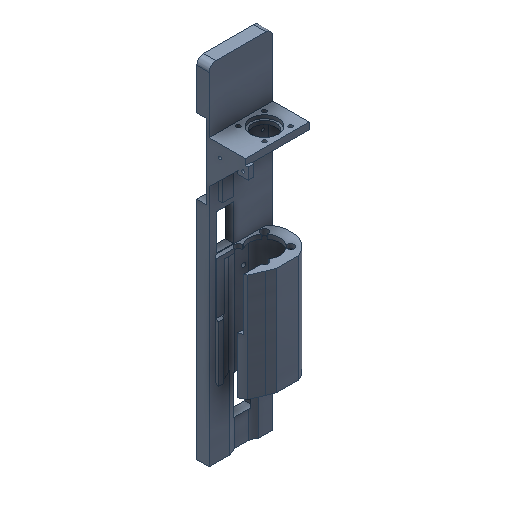
# Autodesk Inventor part: OT2-Pipette V0.5 - frame
Saved by Autodesk Inventor 2025.5 (Build 295498000, 498)
## iProperties
Created: 2026-11-20
Part Number: OT2-Pipette V0.5 - frame
Material: Generisch
Description: printed frame: mount wall with 3 M3 inserts, sleeve + ledge, header window, motor shelf (PETG/ASA)
Document SubType Name: Modeling
Designer: benir
Density: 1 g/cm^3
Appearance: Light Steel Blue
Author: benir
Autodesk Inventor part; units mm, degrees
ref_plane "WP mount face" through (-9.5, 0, 0) normal (1, 0, 0) x (0, 1, 0)
ref_plane "WP pipette x" through (8.2, 0, 0) normal (1, 0, 0) x (0, 1, 0)
ref_plane "WP pipette z" through (0, 0, -3.46) normal (0, 0, 1) x (1, 0, 0)
ref_plane "WP motor seat" through (0, 119, 0) normal (0, 1, 0) x (-1, 0, 0)
ref_plane "y=ins_top_y" through (0, 46, 0) normal (0, 1, 0) x (-1, 0, 0)
ref_plane "z=ins_z" through (0, 0, 13.25) normal (0, 0, 1) x (1, 0, 0)
ref_plane "z=-ins_z" through (0, 0, -13.25) normal (0, 0, 1) x (1, 0, 0)
ref_plane "y=ins_bot_y" through (0, -43, 0) normal (0, 1, 0) x (-1, 0, 0)
sketch "mount wall" plane through (-9.5, 0, 0) normal (1, 0, 0) x (0, 1, 0)
  line L0 (-49, -18.75) -> (156.35, -18.75)
  line L1 (156.35, -18.75) -> (156.35, 18.75)
  line L2 (156.35, 18.75) -> (-49, 18.75)
  line L3 (-49, 18.75) -> (-49, -18.75)
  line L4 (0, -26.25) -> (0, 26.25) projected
  line L5 (-90.07, 0) -> (197.42, 0) projected
  point P0 (0, 0)
  dimension "d10" = 205.35
  dimension "d11" = 37.5
  dimension "d12" = 49
  dimension "d13" = 18.75
  constraints: 8 end point, 2 parallel, 1 horizontal, 1 perpendicular
  measures "d10" distance of L0.start L0.end
  measures "d11" distance of L2.end L0.start
  measures "d12" horizontal distance of point (0, 0) L2.end
  measures "d13" vertical distance of point (0, 0) L0.start
extrude "Extrusion2" add sketch "mount wall" along normal blind 7.3
fillet "wall top edges" radius 4 2 edges at (-5.85, 156.35, 18.75) (-5.85, 156.35, -18.75)
ref_plane "y=sleeve_y0" through (0, -6, 0) normal (0, 1, 0) x (-1, 0, 0)
sketch "sleeve outline" plane through (0, -6, 0) normal (0, 1, 0) x (-1, 0, 0)
  arc A0 (-20.2, -6.2935) -> (3.8, -6.2935) centre (-8.2, -3.46) ccw construction
  arc A1 (-1.2, 13.79) -> (-15.2, 13.79) centre (-8.2, 2.54) ccw construction
  line L0 (3.8, -6.2935) -> (3.8, 1.71) construction
  line L1 (3.8, 1.71) -> (1.58, 7.29) construction
  line L2 (1.58, 7.29) -> (-1.2, 13.79) construction
  line L3 (-15.2, 13.79) -> (-17.98, 7.29) construction
  line L4 (-17.98, 7.29) -> (-20.2, 1.71) construction
  line L5 (-20.2, 1.71) -> (-20.2, -6.2935) construction
  arc A2 (-23.5, -6.6548) -> (7.1, -6.6548) centre (-8.2, -3.46) ccw
  line L6 (7.1, -6.6548) -> (7.1, 2.3423)
  line L7 (7.1, 2.3423) -> (4.6307, 8.549)
  line L8 (4.6307, 8.549) -> (1.4503, 15.9853)
  arc A3 (1.4503, 15.9853) -> (-17.8503, 15.9853) centre (-8.2, 2.54) ccw
  line L9 (-17.8503, 15.9853) -> (-21.0307, 8.549)
  line L10 (-21.0307, 8.549) -> (-23.5, 2.3423)
  line L11 (-23.5, 2.3423) -> (-23.5, -6.6548)
  point P0 (0, 0)
  dimension "sw_l" = 12.8
  dimension "d18" = 3.46
  dimension "d19" = 8.2
  dimension "d20" = 2.54
  dimension "d21" = 8.2
  dimension "d22" = 6.2935
  dimension "d23" = 20.2
  dimension "d24" = 3.8
  dimension "d25" = 13.79
  dimension "d26" = 15.2
  dimension "d27" = 1.2
  dimension "d28" = 1.71
  dimension "d29" = 3.8
  dimension "d30" = 7.29
  dimension "d31" = 1.58
  dimension "d32" = 7.29
  dimension "d33" = 17.98
  dimension "d34" = 1.71
  dimension "d35" = 20.2
  dimension "d36" = 3.3
  constraints: 24 end point, 8 point on circle, 4 centre point, 7 other
  measures "d18" vertical distance of point (0, 0) A0.centre
  measures "d19" horizontal distance of point (0, 0) A0.centre
  measures "d20" vertical distance of point (0, 0) A1.centre
  measures "d21" horizontal distance of point (0, 0) A1.centre
  measures "d22" vertical distance of point (0, 0) L5.end
  measures "d23" horizontal distance of point (0, 0) L5.end
  measures "d24" horizontal distance of point (0, 0) L0.start
  measures "d25" vertical distance of point (0, 0) L3.start
  measures "d26" horizontal distance of point (0, 0) L3.start
  measures "d27" horizontal distance of point (0, 0) L2.end
  measures "d28" vertical distance of point (0, 0) L0.end
  measures "d29" horizontal distance of point (0, 0) L0.end
  measures "d30" vertical distance of point (0, 0) L1.end
  measures "d31" horizontal distance of point (0, 0) L1.end
  measures "d32" vertical distance of point (0, 0) L3.end
  measures "d33" horizontal distance of point (0, 0) L3.end
  measures "d34" vertical distance of point (0, 0) L4.end
  measures "d35" horizontal distance of point (0, 0) L4.end
  measures "d36" distance between parallel lines of L6 L0
extrude "sleeve and ledge" add sketch "sleeve outline" along normal blind 63.5
ref_plane "y=mot_front - shelf_t" through (0, 115, 0) normal (0, 1, 0) x (-1, 0, 0)
sketch "motor shelf" plane through (0, 115, 0) normal (0, 1, 0) x (-1, 0, 0)
  line L0 (2.7, -18.75) -> (-19.2, -18.75)
  line L1 (-19.2, -18.75) -> (-19.2, 18.75)
  line L2 (-19.2, 18.75) -> (2.7, 18.75)
  line L3 (2.7, 18.75) -> (2.7, -18.75)
  line L4 (0, -26.726) -> (0, 26.726) projected
  line L5 (16.1, 0) -> (-30.1, 0) projected
  point P0 (0, 0)
  dimension "d40" = 21.9
  dimension "d41" = 37.5
  dimension "d42" = 2.7
  dimension "d43" = 18.75
  constraints: 8 end point, 2 parallel, 1 horizontal, 1 perpendicular
  measures "d40" distance of L0.start L0.end
  measures "d41" distance of L2.end L0.start
  measures "d42" horizontal distance of point (0, 0) L2.end
  measures "d43" vertical distance of point (0, 0) L0.start
extrude "Extrusion4" add sketch "motor shelf" along normal blind 4
ref_plane "z=-env_z" through (0, 0, -18.75) normal (0, 0, 1) x (1, 0, 0)
sketch "gusset -z" plane through (0, 0, -18.75) normal (0, 0, 1) x (1, 0, 0)
  line L0 (-2.7, 115) -> (19.2, 115)
  line L1 (19.2, 115) -> (-2.7, 93.6)
  line L2 (-2.7, 93.6) -> (-2.7, 115)
  point P0 (0, 0)
  dimension "d47" = 115
  dimension "d48" = 2.7
  dimension "d49" = 115
  dimension "d50" = 19.2
  dimension "d51" = 93.6
  dimension "d52" = 2.7
  constraints: 6 end point
  measures "d47" vertical distance of point (0, 0) L0.start
  measures "d48" horizontal distance of point (0, 0) L0.start
  measures "d49" vertical distance of point (0, 0) L0.end
  measures "d50" horizontal distance of point (0, 0) L0.end
  measures "d51" vertical distance of point (0, 0) L1.end
  measures "d52" horizontal distance of point (0, 0) L1.end
extrude "Extrusion5" add sketch "gusset -z" along normal blind 2.5
ref_plane "z=env_z - gusset_t" through (0, 0, 16.25) normal (0, 0, 1) x (1, 0, 0)
sketch "gusset +z" plane through (0, 0, 16.25) normal (0, 0, 1) x (1, 0, 0)
  line L0 (-2.7, 115) -> (19.2, 115)
  line L1 (19.2, 115) -> (-2.7, 93.6)
  line L2 (-2.7, 93.6) -> (-2.7, 115)
  point P0 (0, 0)
  dimension "d56" = 115
  dimension "d57" = 2.7
  dimension "d58" = 115
  dimension "d59" = 19.2
  dimension "d60" = 93.6
  dimension "d61" = 2.7
  constraints: 6 end point
  measures "d56" vertical distance of point (0, 0) L0.start
  measures "d57" horizontal distance of point (0, 0) L0.start
  measures "d58" vertical distance of point (0, 0) L0.end
  measures "d59" horizontal distance of point (0, 0) L0.end
  measures "d60" vertical distance of point (0, 0) L1.end
  measures "d61" horizontal distance of point (0, 0) L1.end
extrude "Extrusion6" add sketch "gusset +z" along normal blind 2.5
ref_plane "x=wall_x1 - cut_over" through (-3.2, 0, 0) normal (1, 0, 0) x (0, 1, 0)
sketch "rib" plane through (-3.2, 0, 0) normal (1, 0, 0) x (0, 1, 0)
  line L0 (84, 6.3) -> (115, 6.3)
  line L1 (115, 6.3) -> (115, 13.2)
  line L2 (115, 13.2) -> (84, 13.2)
  line L3 (84, 13.2) -> (84, 6.3)
  line L4 (0, -26.726) -> (0, 26.726) projected
  line L5 (-90.07, 0) -> (197.42, 0) projected
  point P0 (0, 0)
  dimension "d65" = 31
  dimension "d66" = 6.9
  dimension "d67" = 84
  dimension "d68" = 6.3
  constraints: 8 end point, 2 parallel, 1 horizontal, 1 perpendicular
  measures "d65" distance of L0.start L0.end
  measures "d66" distance of L2.end L0.start
  measures "d67" horizontal distance of point (0, 0) L2.end
  measures "d68" vertical distance of point (0, 0) L0.start
extrude "rib behind the top-block relief" add sketch "rib" along normal blind 3.2
ref_plane "y=body_bottom - body_cut_below" through (0, -96, 0) normal (0, 1, 0) x (-1, 0, 0)
sketch "body clearance outline" plane through (0, -96, 0) normal (0, 1, 0) x (-1, 0, 0)
  arc A0 (-20.2, -6.2935) -> (3.8, -6.2935) centre (-8.2, -3.46) ccw construction
  arc A1 (-1.2, 13.79) -> (-15.2, 13.79) centre (-8.2, 2.54) ccw construction
  line L0 (3.8, -6.2935) -> (3.8, 1.71) construction
  line L1 (3.8, 1.71) -> (1.58, 7.29) construction
  line L2 (1.58, 7.29) -> (-1.2, 13.79) construction
  line L3 (-15.2, 13.79) -> (-17.98, 7.29) construction
  line L4 (-17.98, 7.29) -> (-20.2, 1.71) construction
  line L5 (-20.2, 1.71) -> (-20.2, -6.2935) construction
  arc A2 (-20.5, -6.3283) -> (4.1, -6.3283) centre (-8.2, -3.46) ccw
  line L6 (4.1, -6.3283) -> (4.1, 1.7675)
  line L7 (4.1, 1.7675) -> (1.8573, 7.4045)
  line L8 (1.8573, 7.4045) -> (-0.9611, 13.9943)
  arc A3 (-0.9611, 13.9943) -> (-15.4389, 13.9943) centre (-8.2, 2.54) ccw
  line L9 (-15.4389, 13.9943) -> (-18.2573, 7.4045)
  line L10 (-18.2573, 7.4045) -> (-20.5, 1.7675)
  line L11 (-20.5, 1.7675) -> (-20.5, -6.3283)
  point P0 (0, 0)
  dimension "d72" = 3.46
  dimension "d73" = 8.2
  dimension "d74" = 2.54
  dimension "d75" = 8.2
  dimension "d76" = 6.2935
  dimension "d77" = 20.2
  dimension "d78" = 3.8
  dimension "d79" = 13.79
  dimension "d80" = 15.2
  dimension "d81" = 1.2
  dimension "d82" = 1.71
  dimension "d83" = 3.8
  dimension "d84" = 7.29
  dimension "d85" = 1.58
  dimension "d86" = 7.29
  dimension "d87" = 17.98
  dimension "d88" = 1.71
  dimension "d89" = 20.2
  dimension "d90" = 0.3
  constraints: 24 end point, 8 point on circle, 4 centre point, 7 other
  measures "d72" vertical distance of point (0, 0) A0.centre
  measures "d73" horizontal distance of point (0, 0) A0.centre
  measures "d74" vertical distance of point (0, 0) A1.centre
  measures "d75" horizontal distance of point (0, 0) A1.centre
  measures "d76" vertical distance of point (0, 0) L5.end
  measures "d77" horizontal distance of point (0, 0) L5.end
  measures "d78" horizontal distance of point (0, 0) L0.start
  measures "d79" vertical distance of point (0, 0) L3.start
  measures "d80" horizontal distance of point (0, 0) L3.start
  measures "d81" horizontal distance of point (0, 0) L2.end
  measures "d82" vertical distance of point (0, 0) L0.end
  measures "d83" horizontal distance of point (0, 0) L0.end
  measures "d84" vertical distance of point (0, 0) L1.end
  measures "d85" horizontal distance of point (0, 0) L1.end
  measures "d86" vertical distance of point (0, 0) L3.end
  measures "d87" horizontal distance of point (0, 0) L3.end
  measures "d88" vertical distance of point (0, 0) L4.end
  measures "d89" horizontal distance of point (0, 0) L4.end
  measures "d90" distance between parallel lines of L6 L0
extrude "body clearance" cut sketch "body clearance outline" along normal blind 151
ref_plane "y=body_top - cut_over" through (0, 54, 0) normal (0, 1, 0) x (-1, 0, 0)
sketch "knob hole" plane through (0, 54, 0) normal (0, 1, 0) x (-1, 0, 0)
  circle A0 centre (-8.2, -3.46) radius 9.1
  point P0 (0, 0)
  dimension "d94" = 3.46
  dimension "d95" = 8.2
  dimension "d96" = 18.2
  constraints: 1 centre point
  measures "d94" vertical distance of point (0, 0) A0.centre
  measures "d95" horizontal distance of point (0, 0) A0.centre
  measures "d96" diameter of A0
extrude "Extrusion9" cut sketch "knob hole" along normal blind 4.5
ref_plane "y=sleeve_y0 - cut_over" through (0, -7, 0) normal (0, 1, 0) x (-1, 0, 0)
sketch "ejector slot" plane through (0, -7, 0) normal (0, 1, 0) x (-1, 0, 0)
  line L0 (-2.6, 8.34) -> (-13.8, 8.34)
  line L1 (-13.8, 8.34) -> (-13.8, 19.75)
  line L2 (-13.8, 19.75) -> (-2.6, 19.75)
  line L3 (-2.6, 19.75) -> (-2.6, 8.34)
  line L4 (0, -26.858) -> (0, 27.518) projected
  line L5 (16.1, 0) -> (-30.1, 0) projected
  point P0 (0, 0)
  dimension "d100" = 11.2
  dimension "d101" = 11.41
  dimension "d102" = 2.6
  dimension "d103" = 8.34
  constraints: 8 end point, 2 parallel, 1 horizontal, 1 perpendicular
  measures "d100" distance of L0.start L0.end
  measures "d101" distance of L2.end L0.start
  measures "d102" horizontal distance of point (0, 0) L2.end
  measures "d103" vertical distance of point (0, 0) L0.start
extrude "ejector button slot" cut sketch "ejector slot" along normal blind 62
ref_plane "y=body_top - eject_win_h" through (0, 27, 0) normal (0, 1, 0) x (-1, 0, 0)
sketch "eject window" plane through (0, 27, 0) normal (0, 1, 0) x (-1, 0, 0)
  line L0 (-0.2, 5.04) -> (-16.2, 5.04)
  line L1 (-16.2, 5.04) -> (-16.2, 19.75)
  line L2 (-16.2, 19.75) -> (-0.2, 19.75)
  line L3 (-0.2, 19.75) -> (-0.2, 5.04)
  line L4 (0, -26.858) -> (0, 27.518) projected
  line L5 (16.1, 0) -> (-30.1, 0) projected
  point P0 (0, 0)
  dimension "d107" = 16
  dimension "d108" = 14.71
  dimension "d109" = 0.2
  dimension "d110" = 5.04
  constraints: 8 end point, 2 parallel, 1 horizontal, 1 perpendicular
  measures "d107" distance of L0.start L0.end
  measures "d108" distance of L2.end L0.start
  measures "d109" horizontal distance of point (0, 0) L2.end
  measures "d110" vertical distance of point (0, 0) L0.start
extrude "Extrusion11" cut sketch "eject window" along normal blind 31.5
sketch "ledge relief" plane through (0, 54, 0) normal (0, 1, 0) x (-1, 0, 0)
  line L0 (-0.5, -3.46) -> (-15.9, -3.46)
  line L1 (-15.9, -3.46) -> (-15.9, 5.04)
  line L2 (-15.9, 5.04) -> (-0.5, 5.04)
  line L3 (-0.5, 5.04) -> (-0.5, -3.46)
  line L4 (0, -26.658) -> (0, 26.318) projected
  line L5 (16.1, 0) -> (-30.1, 0) projected
  point P0 (0, 0)
  dimension "d113" = 15.4
  dimension "d114" = 8.5
  dimension "d115" = 0.5
  dimension "d116" = 3.46
  constraints: 8 end point, 2 parallel, 1 horizontal, 1 perpendicular
  measures "d113" distance of L0.start L0.end
  measures "d114" distance of L2.end L0.start
  measures "d115" horizontal distance of point (0, 0) L2.end
  measures "d116" vertical distance of point (0, 0) L0.start
extrude "Extrusion12" cut sketch "ledge relief" along normal blind 4.5
ref_plane "y=body_bottom + disp_y0" through (0, -33, 0) normal (0, 1, 0) x (-1, 0, 0)
sketch "volume window" plane through (0, -33, 0) normal (0, 1, 0) x (-1, 0, 0)
  line L0 (10.5, -9.46) -> (3.8, -9.46)
  line L1 (3.8, -9.46) -> (3.8, 2.54)
  line L2 (3.8, 2.54) -> (10.5, 2.54)
  line L3 (10.5, 2.54) -> (10.5, -9.46)
  line L4 (0, -26.658) -> (0, 26.318) projected
  line L5 (17.3, 0) -> (-30.3, 0) projected
  point P0 (0, 0)
  dimension "d120" = 6.7
  dimension "d121" = 12
  dimension "d122" = 10.5
  dimension "d123" = 9.46
  constraints: 8 end point, 2 parallel, 1 horizontal, 1 perpendicular
  measures "d120" distance of L0.start L0.end
  measures "d121" distance of L2.end L0.start
  measures "d122" horizontal distance of point (0, 0) L2.end
  measures "d123" vertical distance of point (0, 0) L0.start
extrude "Extrusion13" cut sketch "volume window" along normal blind 23
ref_plane "x=mount_x - cut_over" through (-10.5, 0, 0) normal (1, 0, 0) x (0, 1, 0)
sketch "insert holes" plane through (-10.5, 0, 0) normal (1, 0, 0) x (0, 1, 0)
  circle A0 centre (46, 13.25) radius 2.05
  circle A1 centre (46, -13.25) radius 2.05
  circle A2 centre (-43, -13.25) radius 2.05
  point P0 (0, 0)
  dimension "d127" = 13.25
  dimension "d128" = 46
  dimension "d129" = 4.1
  dimension "d130" = 13.25
  dimension "d131" = 46
  dimension "d132" = 4.1
  dimension "d133" = 13.25
  dimension "d134" = 43
  dimension "d135" = 4.1
  constraints: 3 centre point
  measures "d127" vertical distance of point (0, 0) A0.centre
  measures "d128" horizontal distance of point (0, 0) A0.centre
  measures "d129" diameter of A0
  measures "d130" vertical distance of point (0, 0) A1.centre
  measures "d131" horizontal distance of point (0, 0) A1.centre
  measures "d132" diameter of A1
  measures "d133" vertical distance of point (0, 0) A2.centre
  measures "d134" horizontal distance of point (0, 0) A2.centre
  measures "d135" diameter of A2
extrude "Extrusion14" cut sketch "insert holes" along normal blind 7.7
sketch "insert recesses" plane through (-10.5, 0, 0) normal (1, 0, 0) x (0, 1, 0)
  circle A0 centre (46, 13.25) radius 3
  circle A1 centre (46, -13.25) radius 3
  circle A2 centre (-43, -13.25) radius 3
  point P0 (0, 0)
  dimension "d138" = 13.25
  dimension "d139" = 46
  dimension "d140" = 6
  dimension "d141" = 13.25
  dimension "d142" = 46
  dimension "d143" = 6
  dimension "d144" = 13.25
  dimension "d145" = 43
  dimension "d146" = 6
  constraints: 3 centre point
  measures "d138" vertical distance of point (0, 0) A0.centre
  measures "d139" horizontal distance of point (0, 0) A0.centre
  measures "d140" diameter of A0
  measures "d141" vertical distance of point (0, 0) A1.centre
  measures "d142" horizontal distance of point (0, 0) A1.centre
  measures "d143" diameter of A1
  measures "d144" vertical distance of point (0, 0) A2.centre
  measures "d145" horizontal distance of point (0, 0) A2.centre
  measures "d146" diameter of A2
extrude "Extrusion15" cut sketch "insert recesses" along normal blind 1.3
sketch "grub screw holes" plane through (-10.5, 0, 0) normal (1, 0, 0) x (0, 1, 0)
  circle A0 centre (4, -3.46) radius 1.25
  circle A1 centre (42, -3.46) radius 1.25
  point P0 (0, 0)
  dimension "d149" = 3.46
  dimension "d150" = 4
  dimension "d151" = 2.5
  dimension "d152" = 3.46
  dimension "d153" = 42
  dimension "d154" = 2.5
  constraints: 2 centre point
  measures "d149" vertical distance of point (0, 0) A0.centre
  measures "d150" horizontal distance of point (0, 0) A0.centre
  measures "d151" diameter of A0
  measures "d152" vertical distance of point (0, 0) A1.centre
  measures "d153" horizontal distance of point (0, 0) A1.centre
  measures "d154" diameter of A1
extrude "M3 grub screw holes" cut sketch "grub screw holes" along normal blind 7.7
ref_plane "y=mot_front - mot_pilot_h - pilot_clr" through (0, 117.1, 0) normal (0, 1, 0) x (-1, 0, 0)
sketch "motor pilot recess" plane through (0, 117.1, 0) normal (0, 1, 0) x (-1, 0, 0)
  circle A0 centre (-8.2, -3.46) radius 8.2
  point P0 (0, 0)
  dimension "d158" = 3.46
  dimension "d159" = 8.2
  dimension "d160" = 16.4
  constraints: 1 centre point
  measures "d158" vertical distance of point (0, 0) A0.centre
  measures "d159" horizontal distance of point (0, 0) A0.centre
  measures "d160" diameter of A0
extrude "Extrusion17" cut sketch "motor pilot recess" along normal blind 2.9
ref_plane "y=mot_front - shelf_t - cut_over" through (0, 114, 0) normal (0, 1, 0) x (-1, 0, 0)
sketch "motor boss hole" plane through (0, 114, 0) normal (0, 1, 0) x (-1, 0, 0)
  circle A0 centre (-8.2, -3.46) radius 6.9
  point P0 (0, 0)
  dimension "d164" = 3.46
  dimension "d165" = 8.2
  dimension "d166" = 13.8
  constraints: 1 centre point
  measures "d164" vertical distance of point (0, 0) A0.centre
  measures "d165" horizontal distance of point (0, 0) A0.centre
  measures "d166" diameter of A0
extrude "Extrusion18" cut sketch "motor boss hole" along normal blind 6
sketch "motor screw holes" plane through (0, 114, 0) normal (0, 1, 0) x (-1, 0, 0)
  circle A0 centre (-0.5, -11.16) radius 1.2
  circle A1 centre (-0.5, 4.24) radius 1.2
  circle A2 centre (-15.9, -11.16) radius 1.2
  circle A3 centre (-15.9, 4.24) radius 1.2
  point P0 (0, 0)
  dimension "d169" = 11.16
  dimension "d170" = 0.5
  dimension "d171" = 2.4
  dimension "d172" = 4.24
  dimension "d173" = 0.5
  dimension "d174" = 2.4
  dimension "d175" = 11.16
  dimension "d176" = 15.9
  dimension "d177" = 2.4
  dimension "d178" = 4.24
  dimension "d179" = 15.9
  dimension "d180" = 2.4
  constraints: 4 centre point
  measures "d169" vertical distance of point (0, 0) A0.centre
  measures "d170" horizontal distance of point (0, 0) A0.centre
  measures "d171" diameter of A0
  measures "d172" vertical distance of point (0, 0) A1.centre
  measures "d173" horizontal distance of point (0, 0) A1.centre
  measures "d174" diameter of A1
  measures "d175" vertical distance of point (0, 0) A2.centre
  measures "d176" horizontal distance of point (0, 0) A2.centre
  measures "d177" diameter of A2
  measures "d178" vertical distance of point (0, 0) A3.centre
  measures "d179" horizontal distance of point (0, 0) A3.centre
  measures "d180" diameter of A3
extrude "4 x M2 motor screw holes" cut sketch "motor screw holes" along normal blind 6
sketch "screwdriver channels" plane through (0, 54, 0) normal (0, 1, 0) x (-1, 0, 0)
  circle A0 centre (-0.5, -11.16) radius 2.2
  circle A1 centre (-0.5, 4.24) radius 2.2
  circle A2 centre (-15.9, -11.16) radius 2.2
  circle A3 centre (-15.9, 4.24) radius 2.2
  point P0 (0, 0)
  dimension "d183" = 11.16
  dimension "d184" = 0.5
  dimension "d185" = 4.4
  dimension "d186" = 4.24
  dimension "d187" = 0.5
  dimension "d188" = 4.4
  dimension "d189" = 11.16
  dimension "d190" = 15.9
  dimension "d191" = 4.4
  dimension "d192" = 4.24
  dimension "d193" = 15.9
  dimension "d194" = 4.4
  constraints: 4 centre point
  measures "d183" vertical distance of point (0, 0) A0.centre
  measures "d184" horizontal distance of point (0, 0) A0.centre
  measures "d185" diameter of A0
  measures "d186" vertical distance of point (0, 0) A1.centre
  measures "d187" horizontal distance of point (0, 0) A1.centre
  measures "d188" diameter of A1
  measures "d189" vertical distance of point (0, 0) A2.centre
  measures "d190" horizontal distance of point (0, 0) A2.centre
  measures "d191" diameter of A2
  measures "d192" vertical distance of point (0, 0) A3.centre
  measures "d193" horizontal distance of point (0, 0) A3.centre
  measures "d194" diameter of A3
extrude "Extrusion20" cut sketch "screwdriver channels" along normal blind 62
sketch "plug pocket" plane through (-10.5, 0, 0) normal (1, 0, 0) x (0, 1, 0)
  line L0 (54, 1) -> (83, 1)
  line L1 (83, 1) -> (83, 17.6)
  line L2 (83, 17.6) -> (54, 17.6)
  line L3 (54, 17.6) -> (54, 1)
  line L4 (0, -26.658) -> (0, 26.318) projected
  line L5 (-90.07, 0) -> (197.42, 0) projected
  point P0 (0, 0)
  dimension "d197" = 29
  dimension "d198" = 16.6
  dimension "d199" = 54
  dimension "d200" = 1
  constraints: 8 end point, 2 parallel, 1 horizontal, 1 perpendicular
  measures "d197" distance of L0.start L0.end
  measures "d198" distance of L2.end L0.start
  measures "d199" horizontal distance of point (0, 0) L2.end
  measures "d200" vertical distance of point (0, 0) L0.start
extrude "pocket for the robot's plug holder" cut sketch "plug pocket" along normal blind 3.5
sketch "header window" plane through (-10.5, 0, 0) normal (1, 0, 0) x (0, 1, 0)
  line L0 (57.9, 4.45) -> (79.1, 4.45)
  line L1 (79.1, 4.45) -> (79.1, 14.15)
  line L2 (79.1, 14.15) -> (57.9, 14.15)
  line L3 (57.9, 14.15) -> (57.9, 4.45)
  line L4 (0, -26.658) -> (0, 26.318) projected
  line L5 (-90.07, 0) -> (197.42, 0) projected
  point P0 (0, 0)
  dimension "d203" = 21.2
  dimension "d204" = 9.7
  dimension "d205" = 57.9
  dimension "d206" = 4.45
  constraints: 8 end point, 2 parallel, 1 horizontal, 1 perpendicular
  measures "d203" distance of L0.start L0.end
  measures "d204" distance of L2.end L0.start
  measures "d205" horizontal distance of point (0, 0) L2.end
  measures "d206" vertical distance of point (0, 0) L0.start
extrude "2x5 header window" cut sketch "header window" along normal blind 9.3
sketch "top-block relief" plane through (-10.5, 0, 0) normal (1, 0, 0) x (0, 1, 0)
  line L0 (84, -5) -> (128, -5)
  line L1 (128, -5) -> (128, 19.75)
  line L2 (128, 19.75) -> (84, 19.75)
  line L3 (84, 19.75) -> (84, -5)
  line L4 (0, -26.858) -> (0, 27.518) projected
  line L5 (-90.07, 0) -> (197.42, 0) projected
  point P0 (0, 0)
  dimension "d209" = 44
  dimension "d210" = 24.75
  dimension "d211" = 84
  dimension "d212" = 5
  constraints: 8 end point, 2 parallel, 1 horizontal, 1 perpendicular
  measures "d209" distance of L0.start L0.end
  measures "d210" distance of L2.end L0.start
  measures "d211" horizontal distance of point (0, 0) L2.end
  measures "d212" vertical distance of point (0, 0) L0.start
extrude "relief for the mount's top block" cut sketch "top-block relief" along normal blind 6.5
ref_plane "z=brd_z_front" through (0, 0, 15.35) normal (0, 0, 1) x (1, 0, 0)
sketch "XIAO pin clearance" plane through (0, 0, 15.35) normal (0, 0, 1) x (1, 0, 0)
  line L0 (-0.2, 88.5) -> (22.8, 88.5)
  line L1 (22.8, 88.5) -> (22.8, 109.5)
  line L2 (22.8, 109.5) -> (-0.2, 109.5)
  line L3 (-0.2, 109.5) -> (-0.2, 88.5)
  line L4 (0, -90.07) -> (0, 197.42) projected
  line L5 (-16.1, 0) -> (30.1, 0) projected
  point P0 (0, 0)
  dimension "d216" = 23
  dimension "d217" = 21
  dimension "d218" = 0.2
  dimension "d219" = 88.5
  constraints: 8 end point, 2 parallel, 1 horizontal, 1 perpendicular
  measures "d216" distance of L0.start L0.end
  measures "d217" distance of L2.end L0.start
  measures "d218" horizontal distance of point (0, 0) L2.end
  measures "d219" vertical distance of point (0, 0) L0.start
extrude "Extrusion24" cut sketch "XIAO pin clearance" along normal blind 1.8
sketch "board tabs" plane through (0, 0, 15.35) normal (0, 0, 1) x (1, 0, 0)
  line L0 (14.8, 108.8) -> (20.8, 108.8)
  line L1 (20.8, 108.8) -> (20.8, 115.5)
  line L2 (20.8, 115.5) -> (14.8, 115.5)
  line L3 (14.8, 115.5) -> (14.8, 108.8)
  line L4 (0, -90.07) -> (0, 197.42) projected
  line L5 (-16.1, 0) -> (30.1, 0) projected
  line L6 (1.2, 108.8) -> (7.2, 108.8)
  line L7 (7.2, 108.8) -> (7.2, 115.5)
  line L8 (7.2, 115.5) -> (1.2, 115.5)
  line L9 (1.2, 115.5) -> (1.2, 108.8)
  point P0 (0, 0)
  dimension "d222" = 6
  dimension "d223" = 6.7
  dimension "d224" = 14.8
  dimension "d225" = 108.8
  dimension "d226" = 6
  dimension "d227" = 6.7
  dimension "d228" = 1.2
  dimension "d229" = 108.8
  constraints: 16 end point, 4 parallel, 2 horizontal, 2 perpendicular
  measures "d222" distance of L0.start L0.end
  measures "d223" distance of L2.end L0.start
  measures "d224" horizontal distance of point (0, 0) L2.end
  measures "d225" vertical distance of point (0, 0) L0.start
  measures "d226" distance of L6.start L6.end
  measures "d227" distance of L8.end L6.start
  measures "d228" horizontal distance of point (0, 0) L8.end
  measures "d229" vertical distance of point (0, 0) L6.start
extrude "Extrusion25" add sketch "board tabs" along normal blind 3.4
ref_plane "z=brd_z_front - cut_over" through (0, 0, 14.35) normal (0, 0, 1) x (1, 0, 0)
sketch "board screw holes" plane through (0, 0, 14.35) normal (0, 0, 1) x (1, 0, 0)
  circle A0 centre (17.8, 111.8) radius 0.9
  circle A1 centre (4.2, 111.8) radius 0.9
  point P0 (0, 0)
  dimension "d233" = 111.8
  dimension "d234" = 17.8
  dimension "d235" = 1.8
  dimension "d236" = 111.8
  dimension "d237" = 4.2
  dimension "d238" = 1.8
  constraints: 2 centre point
  measures "d233" vertical distance of point (0, 0) A0.centre
  measures "d234" horizontal distance of point (0, 0) A0.centre
  measures "d235" diameter of A0
  measures "d236" vertical distance of point (0, 0) A1.centre
  measures "d237" horizontal distance of point (0, 0) A1.centre
  measures "d238" diameter of A1
extrude "tool board M2 holes" cut sketch "board screw holes" along normal blind 5.4
ref_plane "x=wall_x1 + cut_over" through (-1.2, 0, 0) normal (1, 0, 0) x (0, 1, 0)
sketch "switch screw holes" plane through (-1.2, 0, 0) normal (1, 0, 0) x (0, 1, 0)
  circle A0 centre (107.3, -12.85) radius 0.9
  circle A1 centre (107.3, -6.35) radius 0.9
  point P0 (0, 0)
  dimension "d242" = 12.85
  dimension "d243" = 107.3
  dimension "d244" = 1.8
  dimension "d245" = 6.35
  dimension "d246" = 107.3
  dimension "d247" = 1.8
  constraints: 2 centre point
  measures "d242" vertical distance of point (0, 0) A0.centre
  measures "d243" horizontal distance of point (0, 0) A0.centre
  measures "d244" diameter of A0
  measures "d245" vertical distance of point (0, 0) A1.centre
  measures "d246" horizontal distance of point (0, 0) A1.centre
  measures "d247" diameter of A1
extrude "Extrusion27" cut sketch "switch screw holes" against normal blind 7
ref_plane "y=plate_y0 - cut_over" through (0, -50, 0) normal (0, 1, 0) x (-1, 0, 0)
sketch "GEN2 outline trim" plane through (0, -50, 0) normal (0, 1, 0) x (-1, 0, 0)
  line L0 (59.5, -68.75) -> (-72.84, -68.75)
  line L1 (-72.84, -68.75) -> (-72.84, 68.75)
  line L2 (-72.84, 68.75) -> (59.5, 68.75)
  line L3 (59.5, 68.75) -> (59.5, -68.75)
  line L4 (0, -96.25) -> (0, 96.25) projected
  line L5 (85.968, 0) -> (-99.308, 0) projected
  line L6 (9.5, -18.75) -> (-22.84, -18.75)
  line L7 (-22.84, -18.75) -> (-22.84, 18.75)
  line L8 (-22.84, 18.75) -> (9.5, 18.75)
  line L9 (9.5, 18.75) -> (9.5, -18.75)
  point P0 (0, 0)
  dimension "d251" = 132.34
  dimension "d252" = 137.5
  dimension "d253" = 59.5
  dimension "d254" = 68.75
  dimension "d255" = 32.34
  dimension "d256" = 37.5
  dimension "d257" = 9.5
  dimension "d258" = 18.75
  constraints: 16 end point, 4 parallel, 2 horizontal, 2 perpendicular
  measures "d251" distance of L0.start L0.end
  measures "d252" distance of L2.end L0.start
  measures "d253" horizontal distance of point (0, 0) L2.end
  measures "d254" vertical distance of point (0, 0) L0.start
  measures "d255" distance of L6.start L6.end
  measures "d256" distance of L8.end L6.start
  measures "d257" horizontal distance of point (0, 0) L8.end
  measures "d258" vertical distance of point (0, 0) L6.start
extrude "trim to the GEN2 outline" cut sketch "GEN2 outline trim" along normal through all both and the other way through all contours L0 L4 L6 L9 L5 L3 | L0 L1 L5 L7 L6 L4 | L5 L9 L8 L4 L2 L3 | L1 L2 L4 L8 L7 L5
equation "\"d10\" = mot_rear - plate_y0"
equation "\"d11\" = 2 * env_z"
equation "\"d12\" = -plate_y0"
equation "\"d13\" = env_z"
equation "\"d14\" = wall_x1 - mount_x"
equation "\"d16\" = wall_fillet"
equation "\"d18\" = -pip_z"
equation "\"d19\" = pip_x"
equation "\"d20\" = pip_z + nose_c"
equation "\"d21\" = pip_x"
equation "\"d23\" = pip_x + body_hw"
equation "\"d24\" = body_hw - pip_x"
equation "\"d26\" = pip_x + nose_hw"
equation "\"d27\" = pip_x - nose_hw"
equation "\"d28\" = pip_z + body_flat_d"
equation "\"d29\" = body_hw - pip_x"
equation "\"d30\" = pip_z + body_ch_d"
equation "\"d31\" = body_ch_w - pip_x"
equation "\"d32\" = pip_z + body_ch_d"
equation "\"d33\" = pip_x + body_ch_w"
equation "\"d34\" = pip_z + body_flat_d"
equation "\"d35\" = pip_x + body_hw"
equation "\"d36\" = wall_out"
equation "\"d37\" = ledge_t + body_top - sleeve_y0"
equation "\"d40\" = shelf_x1 + shelf_back - wall_x1"
equation "\"d41\" = 2 * env_z"
equation "\"d42\" = shelf_back - wall_x1"
equation "\"d43\" = env_z"
equation "\"d44\" = shelf_t"
equation "\"d47\" = mot_front - shelf_t"
equation "\"d48\" = shelf_back - wall_x1"
equation "\"d49\" = mot_front - shelf_t"
equation "\"d50\" = shelf_x1"
equation "\"d51\" = -shelf_t + mot_front - gusset_h"
equation "\"d52\" = shelf_back - wall_x1"
equation "\"d53\" = gusset_t"
equation "\"d56\" = mot_front - shelf_t"
equation "\"d57\" = shelf_back - wall_x1"
equation "\"d58\" = mot_front - shelf_t"
equation "\"d59\" = shelf_x1"
equation "\"d60\" = -shelf_t + mot_front - gusset_h"
equation "\"d61\" = shelf_back - wall_x1"
equation "\"d62\" = gusset_t"
equation "\"d65\" = shelf_y0 - relief_y0"
equation "\"d66\" = rib_z1 - rib_z0"
equation "\"d67\" = relief_y0"
equation "\"d68\" = rib_z0"
equation "\"d69\" = -wall_x1 + rib_x1 + cut_over"
equation "\"d72\" = -pip_z"
equation "\"d73\" = pip_x"
equation "\"d74\" = pip_z + nose_c"
equation "\"d75\" = pip_x"
equation "\"d77\" = pip_x + body_hw"
equation "\"d78\" = body_hw - pip_x"
equation "\"d80\" = pip_x + nose_hw"
equation "\"d81\" = pip_x - nose_hw"
equation "\"d82\" = pip_z + body_flat_d"
equation "\"d83\" = body_hw - pip_x"
equation "\"d84\" = pip_z + body_ch_d"
equation "\"d85\" = body_ch_w - pip_x"
equation "\"d86\" = pip_z + body_ch_d"
equation "\"d87\" = pip_x + body_ch_w"
equation "\"d88\" = pip_z + body_flat_d"
equation "\"d89\" = pip_x + body_hw"
equation "\"d90\" = clr"
equation "\"d91\" = body_len + body_cut_below"
equation "\"d94\" = -pip_z"
equation "\"d95\" = pip_x"
equation "\"d96\" = knob_hole_d"
equation "\"d97\" = ledge_t + 2 * cut_over"
equation "\"d100\" = 2 * ej_slot_clr + 0 * pip_x + 2 * ej_hw"
equation "\"d101\" = cut_over + env_z + ej_slot_z - pip_z - ej_d0"
equation "\"d102\" = -ej_hw + pip_x - ej_slot_clr"
equation "\"d103\" = ej_d0 + pip_z - ej_slot_z"
equation "\"d104\" = -sleeve_y0 + body_top + cut_over"
equation "\"d107\" = 2 * eject_win_hw + 0 * pip_x"
equation "\"d108\" = cut_over + env_z - eject_win_d - pip_z"
equation "\"d109\" = pip_x - eject_win_hw"
equation "\"d110\" = pip_z + eject_win_d"
equation "\"d111\" = ledge_t + eject_win_h + cut_over"
equation "\"d113\" = mot_holes + 0 * pip_x"
equation "\"d114\" = eject_win_d + 0 * pip_z"
equation "\"d115\" = pip_x - 0.5 * mot_holes"
equation "\"d116\" = -pip_z"
equation "\"d117\" = ledge_t + 2 * cut_over"
equation "\"d120\" = -body_hw + pip_x + cut_over - mount_x"
equation "\"d121\" = 2 * disp_hw + 0 * pip_z"
equation "\"d122\" = cut_over - mount_x"
equation "\"d123\" = disp_hw - pip_z"
equation "\"d124\" = disp_y1 - disp_y0"
equation "\"d127\" = ins_z"
equation "\"d128\" = ins_top_y"
equation "\"d129\" = insert_d"
equation "\"d130\" = ins_z"
equation "\"d131\" = ins_top_y"
equation "\"d132\" = insert_d"
equation "\"d133\" = ins_z"
equation "\"d134\" = -ins_bot_y"
equation "\"d135\" = insert_d"
equation "\"d136\" = -mount_x + insert_x_end + cut_over"
equation "\"d138\" = ins_z"
equation "\"d139\" = ins_top_y"
equation "\"d140\" = insert_cb_d"
equation "\"d141\" = ins_z"
equation "\"d142\" = ins_top_y"
equation "\"d143\" = insert_cb_d"
equation "\"d144\" = ins_z"
equation "\"d145\" = -ins_bot_y"
equation "\"d146\" = insert_cb_d"
equation "\"d147\" = insert_cb_h + cut_over"
equation "\"d149\" = -pip_z"
equation "\"d150\" = body_bottom + grub_y1"
equation "\"d151\" = grub_d"
equation "\"d152\" = -pip_z"
equation "\"d153\" = body_bottom + grub_y2"
equation "\"d154\" = grub_d"
equation "\"d155\" = -mount_x - body_hw + pip_x + grub_into + cut_over"
equation "\"d158\" = -pip_z"
equation "\"d159\" = pip_x"
equation "\"d160\" = mot_pilot_d + pilot_clr"
equation "\"d161\" = pilot_clr + mot_pilot_h + cut_over"
equation "\"d164\" = -pip_z"
equation "\"d165\" = pip_x"
equation "\"d166\" = mot_boss_d + boss_clr"
equation "\"d167\" = shelf_t + 2 * cut_over"
equation "\"d169\" = 0.5 * mot_holes - pip_z"
equation "\"d170\" = pip_x - 0.5 * mot_holes"
equation "\"d171\" = m2_clear_d"
equation "\"d172\" = pip_z + 0.5 * mot_holes"
equation "\"d173\" = pip_x - 0.5 * mot_holes"
equation "\"d174\" = m2_clear_d"
equation "\"d175\" = 0.5 * mot_holes - pip_z"
equation "\"d176\" = pip_x + 0.5 * mot_holes"
equation "\"d177\" = m2_clear_d"
equation "\"d178\" = pip_z + 0.5 * mot_holes"
equation "\"d179\" = pip_x + 0.5 * mot_holes"
equation "\"d180\" = m2_clear_d"
equation "\"d181\" = shelf_t + 2 * cut_over"
equation "\"d183\" = 0.5 * mot_holes - pip_z"
equation "\"d184\" = pip_x - 0.5 * mot_holes"
equation "\"d185\" = driver_d"
equation "\"d186\" = pip_z + 0.5 * mot_holes"
equation "\"d187\" = pip_x - 0.5 * mot_holes"
equation "\"d188\" = driver_d"
equation "\"d189\" = 0.5 * mot_holes - pip_z"
equation "\"d190\" = pip_x + 0.5 * mot_holes"
equation "\"d191\" = driver_d"
equation "\"d192\" = pip_z + 0.5 * mot_holes"
equation "\"d193\" = pip_x + 0.5 * mot_holes"
equation "\"d194\" = driver_d"
equation "\"d195\" = -body_top + mot_front - shelf_t + 2 * cut_over"
equation "\"d197\" = plug_pocket_l + 0 * hdr_y"
equation "\"d198\" = plug_pocket_w + 0 * hdr_z"
equation "\"d199\" = hdr_y - 0.5 * plug_pocket_l"
equation "\"d200\" = hdr_z - 0.5 * plug_pocket_w"
equation "\"d201\" = plug_pocket_d + cut_over"
equation "\"d203\" = hdr_l + 0 * hdr_y"
equation "\"d204\" = hdr_w + 0 * hdr_z"
equation "\"d205\" = hdr_y - 0.5 * hdr_l"
equation "\"d206\" = hdr_z - 0.5 * hdr_w"
equation "\"d207\" = -mount_x + wall_x1 + 2 * cut_over"
equation "\"d209\" = relief_y1 - relief_y0"
equation "\"d210\" = cut_over + env_z - relief_z0"
equation "\"d211\" = relief_y0"
equation "\"d212\" = -relief_z0"
equation "\"d213\" = relief_d + cut_over"
equation "\"d217\" = brd_xiao_y1 - brd_xiao_y0"
equation "\"d219\" = brd_xiao_y0"
equation "\"d220\" = brd_back_clr"
equation "\"d222\" = brd_tab_w + 0 * brd_hole_x1"
equation "\"d224\" = brd_hole_x1 - 0.5 * brd_tab_w"
equation "\"d225\" = brd_hole_y - brd_tab_below"
equation "\"d226\" = brd_tab_w + 0 * brd_hole_x2"
equation "\"d228\" = brd_hole_x2 - 0.5 * brd_tab_w"
equation "\"d229\" = brd_hole_y - brd_tab_below"
equation "\"d230\" = env_z - brd_z_front"
equation "\"d233\" = brd_hole_y"
equation "\"d234\" = brd_hole_x1"
equation "\"d235\" = brd_pilot_d"
equation "\"d236\" = brd_hole_y"
equation "\"d237\" = brd_hole_x2"
equation "\"d238\" = brd_pilot_d"
equation "\"d239\" = -brd_z_front + env_z + 2 * cut_over"
equation "\"d242\" = 0.5 * sw_pitch - 0.5 * sw_l - sw_z0"
equation "\"d243\" = sw_h + sw_y0 - sw_hole_down"
equation "\"d244\" = sw_pilot_d"
equation "\"d245\" = -0.5 * sw_pitch - 0.5 * sw_l - sw_z0"
equation "\"d246\" = sw_h + sw_y0 - sw_hole_down"
equation "\"d247\" = sw_pilot_d"
equation "\"d248\" = hole_depth + cut_over"
equation "\"d255\" = env_x1 - mount_x"
equation "\"d256\" = 2 * env_z"
equation "\"d257\" = -mount_x"
equation "\"d258\" = env_z"
equation "\"mot_rear\" = 156.35"
equation "\"plate_y0\" = -49"
equation "\"env_z\" = 18.75"
equation "\"wall_x1\" = -2.2"
equation "\"mount_x\" = -9.5"
equation "\"wall_fillet\" = 4"
equation "\"wall_out\" = 3.3"
equation "\"ledge_t\" = 2.5"
equation "\"body_top\" = 55"
equation "\"sleeve_y0\" = -6"
equation "\"shelf_x1\" = 19.2"
equation "\"shelf_back\" = 0.5"
equation "\"shelf_t\" = 4"
equation "\"gusset_t\" = 2.5"
equation "\"shelf_y0\" = 115"
equation "\"relief_y0\" = 84"
equation "\"rib_z1\" = 13.2"
equation "\"rib_z0\" = 6.3"
equation "\"rib_x1\" = 0"
equation "\"cut_over\" = 1"
equation "\"clr\" = 0.3"
equation "\"body_len\" = 121"
equation "\"body_cut_below\" = 30"
equation "\"knob_hole_d\" = 18.2"
equation "\"ej_slot_clr\" = 0.6"
equation "\"pip_x\" = 8.2"
equation "\"ej_hw\" = 5"
equation "\"ej_slot_z\" = 0.5"
equation "\"pip_z\" = -3.46"
equation "\"ej_d0\" = 12.3"
equation "\"eject_win_hw\" = 8"
equation "\"eject_win_d\" = 8.5"
equation "\"eject_win_h\" = 28"
equation "\"mot_holes\" = 15.4"
equation "\"body_hw\" = 12"
equation "\"disp_hw\" = 6"
equation "\"disp_y1\" = 56"
equation "\"disp_y0\" = 33"
equation "\"insert_d\" = 4.1"
equation "\"insert_x_end\" = -2.8"
equation "\"insert_cb_d\" = 6"
equation "\"insert_cb_h\" = 0.3"
equation "\"grub_d\" = 2.5"
equation "\"grub_into\" = 1"
equation "\"mot_pilot_d\" = 16"
equation "\"pilot_clr\" = 0.4"
equation "\"mot_pilot_h\" = 1.5"
equation "\"mot_boss_d\" = 13"
equation "\"boss_clr\" = 0.8"
equation "\"m2_clear_d\" = 2.4"
equation "\"driver_d\" = 4.4"
equation "\"mot_front\" = 119"
equation "\"plug_pocket_l\" = 29"
equation "\"hdr_y\" = 68.5"
equation "\"plug_pocket_w\" = 16.6"
equation "\"hdr_z\" = 9.3"
equation "\"plug_pocket_d\" = 2.5"
equation "\"hdr_l\" = 21.2"
equation "\"hdr_w\" = 9.7"
equation "\"relief_y1\" = 128"
equation "\"relief_z0\" = -5"
equation "\"relief_d\" = 5.5"
equation "\"brd_xiao_y1\" = 109.5"
equation "\"brd_xiao_y0\" = 88.5"
equation "\"brd_back_clr\" = 1.8"
equation "\"brd_tab_w\" = 6"
equation "\"brd_hole_x1\" = 17.8"
equation "\"brd_hole_x2\" = 4.2"
equation "\"brd_z_front\" = 15.35"
equation "\"brd_pilot_d\" = 1.8"
equation "\"sw_pilot_d\" = 1.8"
equation "\"hole_depth\" = 6"
equation "\"env_x1\" = 22.84"
equation "\"nose_c\" = 6"
equation "\"nose_hw\" = 7"
equation "\"body_flat_d\" = 5.17"
equation "\"body_ch_d\" = 10.75"
equation "\"body_ch_w\" = 9.78"
equation "\"gusset_h\" = 21.4"
equation "\"ins_z\" = 13.25"
equation "\"ins_top_y\" = 46"
equation "\"ins_bot_y\" = -43"
equation "\"body_bottom\" = -66"
equation "\"grub_y1\" = 70"
equation "\"grub_y2\" = 108"
equation "\"brd_hole_y\" = 111.8"
equation "\"brd_tab_below\" = 3"
equation "\"sw_pitch\" = 6.5"
equation "\"sw_z0\" = -16"
equation "\"sw_h\" = 6.5"
equation "\"sw_y0\" = 103.7"
equation "\"sw_hole_down\" = 2.9"
body "Solid2"
